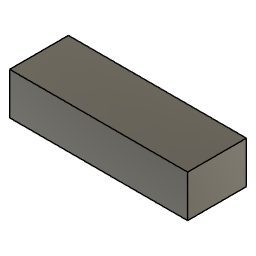
Dustbin Sliding (Autodesk Fusion 360 archive; units mm, degrees)
design "Lipo Battery"
part number: 2025-06-19-18-35-07-415
Autodesk Fusion 360 part; units mm, degrees
box "BoxPrimitive1" add length 35 width 106 height 25 placed x (0, -1, 0) y (1, 0, 0) z (0, 0, 1) at (-19.5433, 31.591, 0)
